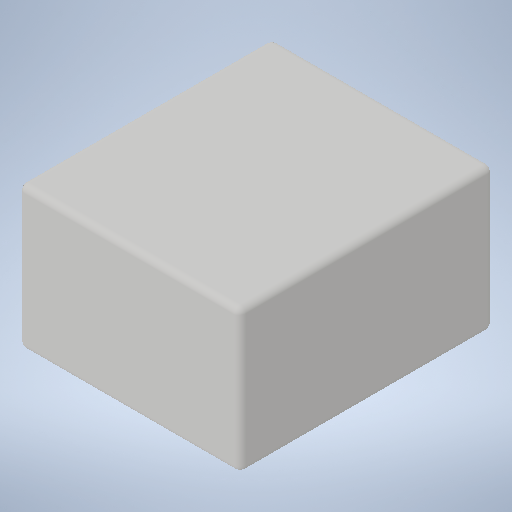
# Autodesk Inventor part: Battery
Saved by Autodesk Inventor 2025.2 (Build 292293000, 293)
## iProperties
Created: 2026-05-20
Part Number: Battery
Material: Generic
Document SubType Name: Modeling
Designer: crazi
Density: 1 g/cm^3
Appearance: Default
Author: crazi
Autodesk Inventor part; units mm, degrees
ref_plane "YZ Plane" through (0, 0, 0) normal (1, 0, 0) x (0, 1, 0)
ref_plane "XZ Plane" through (0, 0, 0) normal (0, 1, 0) x (-1, 0, 0)
ref_plane "XY Plane" through (0, 0, 0) normal (0, 0, 1) x (1, 0, 0)
sketch "Sketch1" plane through (0, 0, 0) normal (0, 1, 0) x (-1, 0, 0)
  line L0 (0, 0) -> (0, -80)
  line L1 (0, -80) -> (-70, -80)
  line L2 (-70, -80) -> (-70, 0)
  line L3 (-70, 0) -> (0, 0)
  dimension "d0" = 80
  dimension "d1" = 70
  constraints: 8 end point, 3 perpendicular, 1 vertical
  measures "d0" distance of L0.start L0.end
  measures "d1" distance of L0.end L1.end
extrude "Extrusion1" add sketch "Sketch1" along normal blind 45
fillet "Fillet1" radius 2 12 edges at (35, 45, 0) (70, 45, -40) (70, 22.5, 0) (70, 0, -40) (35, 0, 0) (35, 45, -80) (70, 22.5, -80) (0, 22.5, -80) (0, 45, -40) (0, 22.5, 0) (0, 0, -40) (35, 0, -80)
body "Solid1"
